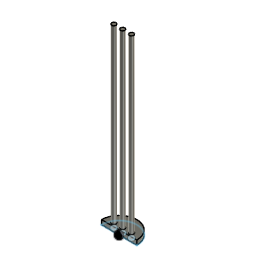
LM35DZ v1 (Autodesk Fusion 360 design; units mm, degrees)
Autodesk Fusion 360 part; units mm, degrees
sketch "草图1" plane through (0, 0, 0) normal (0, 0, 1) x (1, 0, 0)
  line L0 (-2, 0) -> (2, 0)
  arc A0 (2, 0) -> (-2, 0) centre (0, 0) ccw
  circle A1 centre (0, 0.4) radius 0.25
  circle A2 centre (-1, 0.4) radius 0.25
  circle A3 centre (1, 0.4) radius 0.25
  dimension "d2" = 0.5
  dimension "d5" = 1
  dimension "d6" = 0
  constraint coincident A0.centre origin
  constraint horizontal L0
  measures "d2" diameter of A1
extrude "拉伸1" add sketch "草图1" along normal blind 0.5
extrude "拉伸2" add sketch "草图1" along normal blind 20 contours A2
extrude "拉伸3" add sketch "草图1" along normal blind 20 contours A1
extrude "拉伸4" add sketch "草图1" along normal blind 20 contours A3
